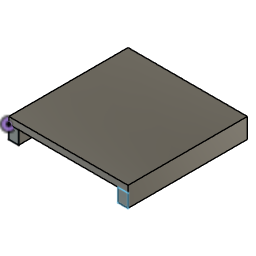
電機控製模塊 (Autodesk Fusion 360 design; units mm, degrees)
Autodesk Fusion 360 part; units mm, degrees
sketch "草图1" plane through (0, 0, 0) normal (0, 0, 1) x (1, 0, 0)
  line L0 (0, 0) -> (18, 0)
  line L1 (18, 0) -> (18, 18)
  line L2 (18, 18) -> (0, 18)
  line L3 (0, 18) -> (0, 0)
  dimension "d1" = 18
  dimension "d2" = 18
  constraint horizontal L0
  constraint vertical L1
  constraint horizontal L2
  constraint vertical L3
  constraint coincident L0.start L3.end
  measures "d1" distance of L0.start L0.end
  measures "d2" distance of L0.start L2.end
extrude "拉伸1" add sketch "草图1" along normal blind 1
sketch "草图2" plane through (0, 0, 0) normal (0, 1, 0) x (1, 0, 0)
  line L0 (0, 0) -> (1.5, 0)
  line L1 (1.5, 0) -> (1.5, 2)
  line L2 (1.5, 2) -> (0, 2)
  line L3 (0, 2) -> (0, 0)
  line L4 (18, 0) -> (16.5, 0)
  line L5 (16.5, 0) -> (16.5, 2)
  line L6 (16.5, 2) -> (18, 2)
  line L7 (18, 2) -> (18, 0)
  dimension "d5" = 1.5
  dimension "d6" = 2
  dimension "d7" = 1.5
  dimension "d8" = 2
  constraint horizontal L0
  constraint vertical L1
  constraint horizontal L2
  constraint vertical L3
  constraint coincident L0.start L3.end
  constraint horizontal L4
  constraint vertical L5
  constraint horizontal L6
  constraint vertical L7
  measures "d5" distance of L0.start L0.end
  measures "d6" distance of L0.start L2.end
  measures "d7" distance of L4.start L4.end
  measures "d8" distance of L4.start L6.end
extrude "拉伸2" add sketch "草图2" along normal blind 18 contours L0 L1 L2 L3
extrude "拉伸3" add sketch "草图2" along normal blind 18 contours L4 L5 L6 L7
